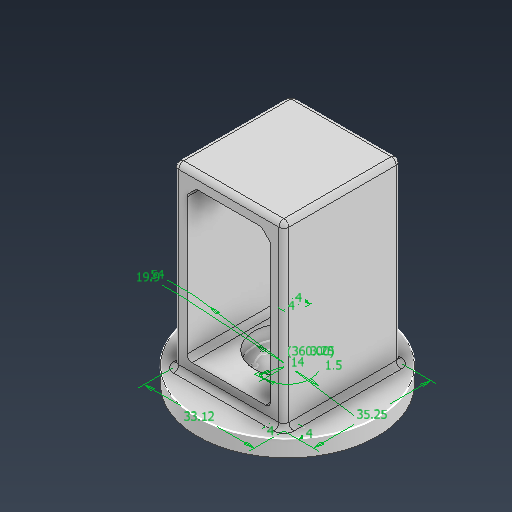
# Autodesk Inventor part: shoudler
Saved by Autodesk Inventor 2026 (Build 300175050, 175E)
## iProperties
Created: 2026-09-23
Part Number: shoudler
Material: Generic
Document SubType Name: Modeling
Designer: PK
Density: 1 g/cm^3
Appearance: Default
Author: PK
Autodesk Inventor part; units mm, degrees
ref_plane "YZ Plane" through (0, 0, 0) normal (1, 0, 0) x (0, 1, 0)
ref_plane "XZ Plane" through (0, 0, 0) normal (0, 1, 0) x (-1, 0, 0)
ref_plane "XY Plane" through (0, 0, 0) normal (0, 0, 1) x (1, 0, 0)
sketch "Sketch1" plane through (0, 0, 0) normal (0, 1, 0) x (-1, 0, 0)
  circle A0 centre (0, 0) radius 27
  circle A1 centre (0, 0) radius 9.95
  line L0 (16.56, -17.625) -> (-16.56, -17.625)
  line L1 (-16.56, -17.625) -> (-16.56, 17.625)
  line L2 (-16.56, 17.625) -> (16.56, 17.625)
  line L3 (16.56, 17.625) -> (16.56, -17.625)
  line L4 (-12.56, -17.625) -> (-12.56, 17.625)
  line L5 (-16.56, 13.625) -> (16.56, 13.625)
  line L6 (12.56, 17.625) -> (12.56, -17.625)
  line L7 (16.56, -13.625) -> (-16.56, -13.625)
  circle A2 centre (0, -7) radius 0.75
  circle A3 centre (0, 0) radius 7
  circle A4 centre (4.9497, -4.9497) radius 0.75
  circle A5 centre (7, 0) radius 0.75
  circle A6 centre (4.9497, 4.9497) radius 0.75
  circle A7 centre (0, 7) radius 0.75
  circle A8 centre (-4.9497, 4.9497) radius 0.75
  circle A9 centre (-7, 0) radius 0.75
  circle A10 centre (-4.9497, -4.9497) radius 0.75
  point P0 (-16.56, 0)
  point P1 (0, -17.625)
  point P2 (-12.56, 13.625)
  point P3 (-12.56, -13.625)
  point P4 (12.56, -13.625)
  point P5 (12.56, 13.625)
  point P6 (1.6206, -9.8171)
  point P7 (0, -7)
  dimension "d2" = 19.9
  dimension "d140" = 14
  dimension "d4" = 33.12
  dimension "d5" = 35.25
  dimension "d6" = 4
  dimension "d7" = 4
  dimension "d8" = 4
  dimension "d9" = 4
  dimension "d94" = 3.25
  dimension "d95" = 1.5
  dimension "d98" = 360
  dimension "d104" = 54
  constraints: 16 end point, 9 centre point, 8 point on line, 5 perpendicular, 5 vertical alignment, 4 coincident, 3 horizontal alignment, 2 midpoint, 2 parallel, 1 horizontal, 22 other
  measures "d4" distance of L1.end L2.end
  measures "d5" distance of L0.end L1.end
  measures "d6" distance of L1.end L4.end
  measures "d7" distance of L5.start L1.end
  measures "d8" distance of L0.start L6.end
  measures "d9" distance of L0.start L7.start
  measures "d94" distance of point (0, -7) point (1.621, -9.817)
  measures "d95" diameter of A2
  measures "d104" diameter of A0
extrude "Extrusion1" add sketch "Sketch1" against normal blind 5 contours A0 | A1 | L0 L6 L7 L3 | L0 L4 L7 L6 | L7 L6 L5 L3 | L0 L1 L7 L4 | L7 L4 L5 L6 | L5 L6 L2 L3 | L7 L1 L5 L4 | L5 L4 L2 L6 | L5 L1 L2 L4 | A2 A3 | A3 A2 | A2 A3 A10 A9 A8 A7 A6 A5 A4 | A4 A3 | A3 A4 | A10 A3 | A3 A10 | A5 A3 | A3 A5 | A9 A3 | A3 A9 | A6 A3 | A3 A6 | A8 A3 | A3 A8 | A7 A3 | A3 A7
extrude "Extrusion2" cut sketch "Sketch1" along normal blind 2.5 from surface at -5 contours A1 | A2 A3 | A3 A2 | A2 A3 A10 A9 A8 A7 A6 A5 A4 | A4 A3 | A3 A4 | A10 A3 | A3 A10 | A5 A3 | A3 A5 | A9 A3 | A3 A9 | A6 A3 | A3 A6 | A8 A3 | A3 A8 | A7 A3 | A3 A7
extrude "Extrusion4" add sketch "Sketch1" along normal blind 53.82 contours A1 | L0 L6 L7 L3 | L0 L4 L7 L6 | L7 L6 L5 L3 | L0 L1 L7 L4 | L7 L4 L5 L6 | L5 L6 L2 L3 | L7 L1 L5 L4 | L5 L4 L2 L6 | L5 L1 L2 L4 | A2 A3 | A3 A2 | A2 A3 A10 A9 A8 A7 A6 A5 A4 | A4 A3 | A3 A4 | A10 A3 | A3 A10 | A5 A3 | A3 A5 | A9 A3 | A3 A9 | A6 A3 | A3 A6 | A8 A3 | A3 A8 | A7 A3 | A3 A7
sketch "Sketch3" plane through (12.56, 0, 17.625) normal (0, 0, 1) x (1, 0, 0)
  line L0 (-29.12, 4) -> (-29.12, 0)
  line L1 (-29.12, 0) -> (4, 0)
  line L2 (-25.12, 4) -> (-25.12, 0)
  line L3 (-2.7, 9.5905) -> (0, 9.5905)
  line L4 (-22.42, 9.5905) -> (-25.12, 9.5905)
  line L5 (-4.7, 5.4025) -> (-4.7, 9.5905)
  line L6 (-20.42, 9.5905) -> (-20.42, 5.4025)
  line L7 (-20.42, 5.4025) -> (-4.7, 5.4025)
  line L8 (-4.7, 5.4025) -> (-4.7, 4)
  line L9 (-20.42, 5.4025) -> (-20.42, 4)
  line L10 (-6.15, 31.7025) -> (-6.15, 28.2905)
  arc A0 (-6.15, 31.7025) -> (-3.453, 35.22) centre (-12.56, 39.41) ccw
  line L11 (0, 33.8) -> (0, 39.8)
  circle A1 centre (-12.56, 39.41) radius 1.1
  circle A2 centre (-12.56, 39.41) radius 3.15
  line L12 (0, 39.8) -> (0, 49.82)
  line L13 (-25.12, 4) -> (-25.12, 49.82)
  line L14 (-29.12, 49.82) -> (-29.12, 4)
  line L15 (4, 0) -> (4, 53.82)
  line L16 (-29.12, 53.82) -> (4, 53.82)
  line L17 (0, 4) -> (0, 13.8)
  line L18 (-29.12, 4) -> (4, 4)
  line L19 (-2.7, 28.2905) -> (-2.7, 20.9905)
  line L20 (-22.42, 28.2905) -> (-2.7, 28.2905)
  line L21 (-22.42, 20.9905) -> (-22.42, 28.2905)
  line L22 (-22.42, 22.7905) -> (-2.7, 22.7905)
  line L23 (0, 13.8) -> (0, 25.3)
  line L24 (-22.42, 20.9905) -> (-2.7, 20.9905)
  line L25 (-2.7, 20.9905) -> (-2.7, 9.5905)
  line L26 (-22.42, 9.5905) -> (-22.42, 20.9905)
  line L27 (-2.7, 9.5905) -> (-22.42, 9.5905)
  line L28 (-25.12, 4) -> (-25.12, 9.5905) construction
  line L29 (0, 25.3) -> (0, 33.8)
  line L30 (-5.61, 4) -> (0, 4) construction
  line L31 (0, 4) -> (0, 0)
  line L32 (-2.7, 28.2905) -> (0, 28.2905)
  line L33 (0, 4) -> (0, 9.71) construction
  line L34 (-3.453, 35.22) -> (0, 35.22)
  line L35 (-2.8, 49.82) -> (0, 47.02)
  line L36 (0, 49.82) -> (0, 53.82)
  line L37 (4, 49.82) -> (-29.12, 49.82)
  line L38 (-29.12, 49.82) -> (-29.12, 53.82)
  line L39 (-22.42, 28.2905) -> (-25.12, 28.2905)
  line L40 (-18.97, 31.7025) -> (-18.97, 28.2905)
  line L41 (-25.12, 47.02) -> (-22.32, 49.82)
  line L42 (-21.667, 35.22) -> (-25.12, 35.22)
  line L43 (-25.12, 49.82) -> (-25.12, 53.82)
  arc A3 (-21.667, 35.22) -> (-18.97, 31.7025) centre (-12.56, 39.41) ccw
  point P0 (-12.56, 0)
  point P1 (-29.12, 26.91)
  point P2 (-12.56, 0)
  point P3 (-6.15, 28.272)
  point P4 (-29.12, 49.52)
  point P5 (4, 26.91)
  point P6 (-24.82, 53.82)
  point P7 (-0.3, 53.82)
  point P8 (-12.56, 53.82)
  point P9 (-3.44, 65.2527)
  point P10 (-3.59, 64.9967)
  dimension "d105" = 4
  dimension "d106" = 25.12
  dimension "d107" = 11.4
  dimension "d108" = 4
  dimension "d109" = 6.3
  dimension "d110" = 2.2
  dimension "d111" = 0.3
  dimension "d112" = 0.3
  dimension "d113" = 0.3
  dimension "d114" = 3.412
  dimension "d115" = 3.412
  dimension "d116" = 5.5
  dimension "d117" = 2
  dimension "d118" = 2
  dimension "d119" = 4.188
  dimension "d120" = 7.3
  dimension "d121" = 2.8
  dimension "d122" = 2.8
  dimension "d123" = 2.8
  dimension "d124" = 2.8
  dimension "d125" = 12.56
  dimension "d126" = 11.8
  dimension "d127" = 3.453
  dimension "d128" = 3.453
  dimension "d129" = 6.15
  dimension "d130" = 2.7
  dimension "d131" = 2.7
  dimension "d132" = 45.82
  dimension "d133" = 4
  dimension "d134" = 4
  dimension "d135" = 4
  dimension "d136" = 4
  dimension "d137" = -0.256
  constraints: 88 end point, 34 point on line, 16 perpendicular, 6 coincident, 5 parallel, 4 centre point, 4 midpoint, 4 point on circle, 1 collinear
  measures "d105" distance of L31.start L18.end
  measures "d106" distance between parallel lines of L23 L13
  measures "d107" distance of L25.start L27.start
  measures "d108" distance between parallel lines of L0 L2
  measures "d109" diameter of A2
  measures "d110" diameter of A1
  measures "d111" distance from line of L43 point (-24.82, 53.82)
  measures "d112" distance from line of L36 point (-0.3, 53.82)
  measures "d113" distance of point (-29.12, 49.52) L37.end
  measures "d114" distance from line of L20 L40.start
  measures "d115" distance from line of L20 L10.start
  measures "d116" distance between parallel lines of L22 L20
  measures "d117" distance from line of L26 L6.start
  measures "d118" distance from line of L25 L5.end
  measures "d119" distance of L6.start L9.start
  measures "d120" distance between parallel lines of L24 L20
  measures "d121" distance of L41.start L13.end
  measures "d122" distance of L13.end L41.end
  measures "d123" distance of L35.start L12.end
  measures "d124" distance of L35.end L12.end
  measures "d125" distance from line of L13 A2.centre
  measures "d126" distance of L42.end L41.start
  measures "d127" distance of L42.start L42.end
  measures "d128" distance from line of L29 L34.start
  measures "d129" distance of L10.end L32.end
  measures "d130" distance of L39.end L20.start
  measures "d131" distance of L32.end L20.end
  measures "d132" distance of L37.end L14.end
  measures "d133" distance of L16.start L37.end
  measures "d134" distance of L0.end L14.end
  measures "d135" distance of L15.start L18.end
  measures "d136" distance of L16.end L37.start
  measures "d137" vertical distance of point (-3.44, 65.253) point (-3.59, 64.997)
extrude "Extrusion5" cut sketch "Sketch3" against normal blind 29 contours L13 L4 L27 L6 L9 L18 | L13 L39 L21 L26 L4 | L9 L7 L8 L18 | L41 L37 L35 L12 L11 L34 A0 L10 L20 L40 A3 L42 L13 | L26 L24 L25 L27 | L13 L42 A3 L40 L20 L39 | L6 L27 L5 L7 | L8 L5 L27 L3 L17 L18 | L21 L22 L19 L24 | L20 L19 L22 L21 | L3 L25 L19 L32 L29 L23 L17 | L10 A0 L34 L11 L29 L32 L20 | A1 | A2
extrude "Extrusion6" cut sketch "Sketch3" against normal blind 3.75 from surface at -29 contours A2
extrude "Extrusion7" cut sketch "Sketch3" against normal blind 1.7 from surface at -29 contours L13 L4 L27 L6 L9 L18 | L13 L39 L21 L26 L4 | L9 L7 L8 L18 | L13 L42 A3 L40 L20 L39 | L6 L27 L5 L7 | L8 L5 L27 L3 L17 L18 | L3 L25 L19 L32 L29 L23 L17 | L10 A0 L34 L11 L29 L32 L20
extrude "Extrusion8" cut sketch "Sketch3" against normal up to surface (3.75 mm away) from surface at -29 contours L26 L24 L25 L27
extrude "Extrusion9" cut sketch "Sketch3" against normal blind 10 from surface at -29 contours L21 L22 L19 L24 | L20 L19 L22 L21
fillet "Fillet1" radius 1.5 18 edges at (0, 0, 17.625) (-16.56, 0, 0) (16.56, 0, 0) (0, 0, -17.625) (-16.56, 26.91, 17.625) (-16.56, 26.91, -17.625) (-16.56, 53.82, 0) (0, 53.82, 17.625) (16.56, 26.91, 17.625) (16.56, 26.91, -17.625) (16.56, 53.82, 0) (0, 53.82, -17.625) (-9.76, 49.82, 3.125) (-12.56, 47.02, 3.125) (9.76, 49.82, 3.125) (12.56, 47.02, 3.125) (-12.56, 4, 2.275) (12.56, 4, 2.275)
extrude "Extrusion10" cut sketch "Sketch1" against normal blind 10 contours A2 A3 | A3 A2 | A4 A3 | A3 A4 | A10 A3 | A3 A10 | A5 A3 | A3 A5 | A9 A3 | A3 A9 | A6 A3 | A3 A6 | A8 A3 | A3 A8 | A7 A3 | A3 A7
extrude "Extrusion12" cut sketch "Sketch1" against normal blind 4 from surface at 4 contours A1 | A2 A3 | A3 A2 | A2 A3 A10 A9 A8 A7 A6 A5 A4 | A4 A3 | A3 A4 | A10 A3 | A3 A10 | A5 A3 | A3 A5 | A9 A3 | A3 A9 | A6 A3 | A3 A6 | A8 A3 | A3 A8 | A7 A3 | A3 A7
body "Solid1"
